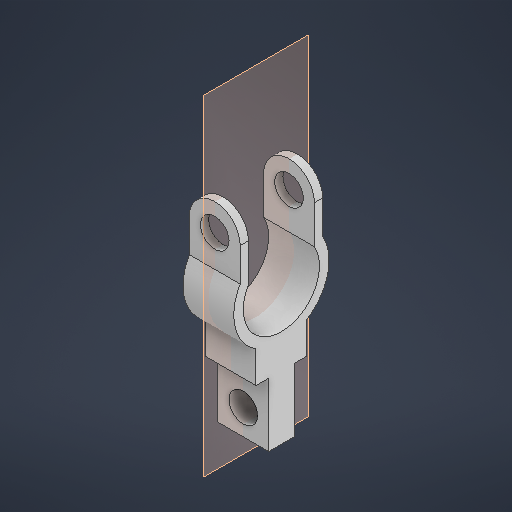
# Autodesk Inventor part: support_de_maintient_incline2petit_tuyau
Saved by Autodesk Inventor 2026 (Build 300175000, 175)
## iProperties
Created: 2025-05-04
Part Number: support_de_maintient_incline2petit_tuyau
Material: Générique
Document SubType Name: Modeling
Designer: virgi
Density: 1 g/cm^3
Appearance: Par défaut
Author: virgi
Autodesk Inventor part; units mm, degrees
ref_plane "YZ Plane" through (0, 0, 0) normal (1, 0, 0) x (0, 1, 0)
ref_plane "XZ Plane" through (0, 0, 0) normal (0, 1, 0) x (-1, 0, 0)
ref_plane "XY Plane" through (0, 0, 0) normal (0, 0, 1) x (1, 0, 0)
sketch "Esquisse1" plane through (0, 0, 0) normal (1, 0, 0) x (0, 1, 0)
  line L0 (10, 4) -> (15, 4)
  line L1 (15, -4) -> (10, -4)
  line L2 (0, -2) -> (10, -2)
  line L3 (10, 2) -> (0, 2)
  line L4 (0, 0) -> (48.1213, 0)
  line L5 (0, 2) -> (0, -2)
  line L6 (10, 2) -> (10, 4)
  line L7 (10, -4) -> (10, -2)
  line L8 (24.3443, 5.1962) -> (34.3443, 5.1962)
  line L9 (25.0943, 6.4952) -> (34.3443, 6.4952)
  line L10 (34.3443, 6.4952) -> (34.3443, 5.1962)
  arc A0 (24.3443, 5.1962) -> (15.3443, 0) centre (21.3443, 0) ccw
  arc A1 (25.0943, 6.4952) -> (15, 4) centre (21.3443, 0) ccw
  line L11 (24.3443, -5.1962) -> (34.3443, -5.1962)
  line L12 (25.0943, -6.4952) -> (34.3443, -6.4952)
  arc A2 (15.3443, 0) -> (24.3443, -5.1962) centre (21.3443, 0) ccw
  arc A3 (15, -4) -> (25.0943, -6.4952) centre (21.3443, 0) ccw
  line L13 (34.3443, -5.1962) -> (34.3443, -6.4952)
  line L14 (24.3443, 5.1962) -> (25.0943, 6.4952)
  point P0 (10, 3)
  dimension "d1" = 4
  dimension "d2" = 10
  dimension "d3" = 8
  dimension "d7" = 1.5
  dimension "d8" = 10
  dimension "d10" = 6
  dimension "d11" = 15
  dimension "d14" = 60
  constraints: 32 end point, 8 point on circle, 4 centre point, 4 symmetric about line, 3 point on line, 3 vertical, 2 coincident, 2 horizontal, 2 midpoint, 2 perpendicular, 1 line through centre, 1 parallel, 4 other
  measures "d1" distance between parallel lines of L2 L3
  measures "d2" distance from line of point (10, 3) L5
  measures "d3" distance between parallel lines of L1 L0
  measures "d7" radial gap between concentric circles of A1 A0
  measures "d8" distance of L8.end L8.start
  measures "d10" radius of A2
  measures "d11" distance from line of L5 L0.end
  measures "d14" angle of L4 L14
extrude "Extrusion1" add sketch "Esquisse1" along normal blind 8
ref_plane "Plan de construction1" through (4, 0, 0) normal (1, 0, 0) x (0, 0, -1)
sketch "Esquisse2" plane through (0, 25.0943, 6.4952) normal (0, 0, 1) x (1, 0, 0)
  line L0 (4, 16.1189) -> (4, -31.9631) projected
  line L1 (0, 0) -> (8, 0) projected
  point P0 (0, -25.0943)
  point P1 (4, 5)
  dimension "d22" = 5
  constraints: 1 point on line
  measures "d22" distance from line of point (4, 5) L1
hole "Perçage1" at (4, 30.0943, 6.4952) direction (0, 0, -1) diameter 4.5 end through all
fillet "Congé1" radius 4 4 edges at (8, 34.3443, -5.8457) (0, 34.3443, -5.8457) (0, 34.3443, 5.8457) (8, 34.3443, 5.8457)
sketch "Esquisse4" plane through (0, 0, -2) normal (0, 0, -1) x (-1, 0, 0)
  line L0 (-4, -6.8689) -> (-4, 41.2131) projected
  line L1 (0, 0) -> (-8, 0) projected
  point P0 (-4, 4)
  dimension "d31" = 4
  constraints: 1 point on line
  measures "d31" distance from line of L1 point (-4, 4)
hole "Perçage2" at (4, 4, -2) direction (0, 0, 1) diameter 4.5 end through all
